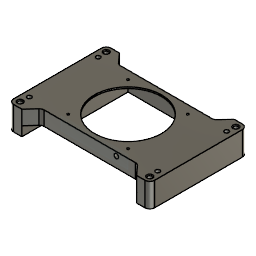
MPPT250 (Autodesk Fusion 360 design; units mm, degrees)
Autodesk Fusion 360 part; units mm, degrees
sketch "Skizze1" plane through (0, 0, 0) normal (0, 0, 1) x (1, 0, 0)
  line L0 (-137.5, 102) -> (137.5, 102)
  line L1 (147.5, 92) -> (147.5, -92)
  line L2 (137.5, -102) -> (-137.5, -102)
  line L3 (-147.5, -92) -> (-147.5, 92)
  line L4 (0, 102) -> (0, -102) construction
  line L5 (-147.5, 0) -> (147.5, 0) construction
  arc A0 (-137.5, 102) -> (-147.5, 92) centre (-137.5, 92) ccw
  arc A1 (-147.5, -92) -> (-137.5, -102) centre (-137.5, -92) ccw
  arc A2 (137.5, -102) -> (147.5, -92) centre (137.5, -92) ccw
  arc A3 (147.5, 92) -> (137.5, 102) centre (137.5, 92) ccw
  point P0 (-147.5, 102)
  point P1 (147.5, 102)
  point P2 (-147.5, -102)
  dimension "d1" = 295
  dimension "d2" = 204
  dimension "d3" = 10
  constraint horizontal L0
  constraint vertical L1
  constraint horizontal L2
  constraint vertical L3
  constraint midpoint L4 origin
  constraint coincident L0 L4.start
  constraint coincident L3 L5.start
  constraint coincident P0 L0
  constraint coincident P0 L3
  constraint tangent L0 A0
  constraint tangent L3 A0
  constraint coincident L2 L4.end
  constraint coincident P2 L2
  constraint coincident P2 L3
  constraint tangent L2 A1
  constraint tangent L3 A1
  constraint equal A0 A1
  constraint coincident L1 L5.end
  constraint tangent L1 A2
  constraint tangent L2 A2
  constraint equal A0 A2
  constraint coincident P1 L0
  constraint coincident P1 L1
  constraint tangent L0 A3
  constraint tangent L1 A3
  constraint equal A0 A3
  measures "d1" distance of P0 P1
  measures "d2" distance of P0 P2
  measures "d3" radius of A0
extrude "Extrusion1" add sketch "Skizze1" along normal blind 50
sketch "Skizze2" plane through (0, 0, 50) normal (0, 0, 1) x (-1, 0, 0)
  arc A0 (-137.5, 102) -> (-147.5, 92) centre (-137.5, 92) ccw
  line L0 (-147.5, 92) -> (-147.5, -92)
  arc A1 (-147.5, -92) -> (-137.5, -102) centre (-137.5, -92) ccw
  line L1 (-137.5, -102) -> (137.5, -102)
  arc A2 (137.5, -102) -> (147.5, -92) centre (137.5, -92) ccw
  line L2 (147.5, -92) -> (147.5, 92)
  arc A3 (147.5, 92) -> (137.5, 102) centre (137.5, 92) ccw
  line L3 (137.5, 102) -> (-137.5, 102)
  line L4 (134.3, -72.05) -> (-134.3, -72.05) construction
  line L5 (-134.3, -72.05) -> (-134.3, 72.05) construction
  line L6 (-134.3, 72.05) -> (134.3, 72.05) construction
  line L7 (134.3, 72.05) -> (134.3, -72.05) construction
  line L8 (134.3, 0) -> (-134.3, 0) construction
  line L9 (0, -72.05) -> (0, 72.05) construction
  dimension "d6" = 268.6
  dimension "d7" = 144.1
  constraint horizontal L4
  constraint vertical L5
  constraint horizontal L6
  constraint vertical L7
  constraint midpoint L7 L8.start
  constraint midpoint L5 L8.end
  constraint midpoint L4 L9.start
  constraint midpoint L6 L9.end
  constraint midpoint L8 origin
  measures "d6" distance of L4.start L4.end
  measures "d7" distance of L4.start L6.end
hole "Bohrung1" at (-134.3, 72.05, 50) at (134.3, 72.05, 50) at (134.3, -72.05, 50) at (-134.3, -72.05, 50) direction (0, 0, -1) diameter 8.8 depth 50 tip angle 180
sketch "Skizze3" plane through (0, 0, 50) normal (0, 0, 1) x (-1, 0, 0)
  circle A0 centre (-134.3, 72.05) radius 4.4
  circle A1 centre (134.3, -72.05) radius 4.4
  circle A2 centre (-134.3, -72.05) radius 4.4
  circle A3 centre (134.3, 72.05) radius 4.4
  arc A4 (-137.5, 102) -> (-147.5, 92) centre (-137.5, 92) ccw
  line L0 (-147.5, 92) -> (-147.5, -92)
  arc A5 (-147.5, -92) -> (-137.5, -102) centre (-137.5, -92) ccw
  line L1 (-137.5, -102) -> (137.5, -102)
  arc A6 (137.5, -102) -> (147.5, -92) centre (137.5, -92) ccw
  line L2 (147.5, -92) -> (147.5, 92)
  arc A7 (147.5, 92) -> (137.5, 102) centre (137.5, 92) ccw
  line L3 (137.5, 102) -> (-137.5, 102)
  line L4 (135.5, -90) -> (-135.5, -90) construction
  line L5 (-135.5, -90) -> (-135.5, 90) construction
  line L6 (-135.5, 90) -> (135.5, 90) construction
  line L7 (135.5, 90) -> (135.5, -90) construction
  line L8 (135.5, 0) -> (-135.5, 0) construction
  line L9 (0, -90) -> (0, 90) construction
  dimension "d11" = 271
  dimension "d12" = 180
  constraint horizontal L4
  constraint vertical L5
  constraint horizontal L6
  constraint vertical L7
  constraint midpoint L7 L8.start
  constraint midpoint L5 L8.end
  constraint midpoint L4 L9.start
  constraint midpoint L6 L9.end
  constraint midpoint L8 origin
  measures "d11" distance of L4.start L4.end
  measures "d12" distance of L4.start L6.end
hole "Bohrung2" at (-135.5, 90, 50) at (-135.5, -90, 50) at (135.5, -90, 50) at (135.5, 90, 50) direction (0, 0, -1) diameter 8.8 depth 50 tip angle 180 countersink diameter 12 countersink angle 90
sketch "Skizze4" plane through (0, 0, 50) normal (0, 0, 1) x (-1, 0, 0)
  circle A0 centre (-135.5, 90) radius 6
  circle A1 centre (135.5, -90) radius 6
  circle A2 centre (135.5, 90) radius 6
  circle A3 centre (-135.5, -90) radius 6
  circle A4 centre (-134.3, 72.05) radius 4.4
  circle A5 centre (134.3, -72.05) radius 4.4
  circle A6 centre (-134.3, -72.05) radius 4.4
  circle A7 centre (134.3, 72.05) radius 4.4
  arc A8 (-137.5, 102) -> (-147.5, 92) centre (-137.5, 92) ccw
  line L0 (-147.5, 92) -> (-147.5, -92)
  arc A9 (-147.5, -92) -> (-137.5, -102) centre (-137.5, -92) ccw
  line L1 (-137.5, -102) -> (137.5, -102)
  arc A10 (137.5, -102) -> (147.5, -92) centre (137.5, -92) ccw
  line L2 (147.5, -92) -> (147.5, 92)
  arc A11 (147.5, 92) -> (137.5, 102) centre (137.5, 92) ccw
  line L3 (137.5, 102) -> (-137.5, 102)
hole "Bohrung3" at (0, 0, 50) direction (0, 0, -1) diameter 140 depth 50 tip angle 180
sketch "Skizze5" plane through (0, 0, 50) normal (0, 0, 1) x (-1, 0, 0)
  circle A0 centre (0, 0) radius 70
  circle A1 centre (-135.5, 90) radius 6
  circle A2 centre (135.5, -90) radius 6
  circle A3 centre (135.5, 90) radius 6
  circle A4 centre (-135.5, -90) radius 6
  circle A5 centre (-134.3, 72.05) radius 4.4
  circle A6 centre (134.3, -72.05) radius 4.4
  circle A7 centre (-134.3, -72.05) radius 4.4
  circle A8 centre (134.3, 72.05) radius 4.4
  arc A9 (-137.5, 102) -> (-147.5, 92) centre (-137.5, 92) ccw
  line L0 (-147.5, 92) -> (-147.5, -92)
  arc A10 (-147.5, -92) -> (-137.5, -102) centre (-137.5, -92) ccw
  line L1 (-137.5, -102) -> (137.5, -102)
  arc A11 (137.5, -102) -> (147.5, -92) centre (137.5, -92) ccw
  line L2 (147.5, -92) -> (147.5, 92)
  arc A12 (147.5, 92) -> (137.5, 102) centre (137.5, 92) ccw
  line L3 (137.5, 102) -> (-137.5, 102)
  line L4 (62.5, -62.5) -> (-62.5, -62.5) construction
  line L5 (-62.5, -62.5) -> (-62.5, 62.5) construction
  line L6 (-62.5, 62.5) -> (62.5, 62.5) construction
  line L7 (62.5, 62.5) -> (62.5, -62.5) construction
  line L8 (62.5, 0) -> (-62.5, 0) construction
  line L9 (0, -62.5) -> (0, 62.5) construction
  dimension "d21" = 125
  dimension "d22" = 125
  constraint horizontal L4
  constraint vertical L5
  constraint horizontal L6
  constraint vertical L7
  constraint midpoint L7 L8.start
  constraint midpoint L5 L8.end
  constraint midpoint L4 L9.start
  constraint midpoint L6 L9.end
  constraint midpoint L9 A0.centre
  constraint coincident A0.centre origin
  measures "d21" distance of L4.start L4.end
  measures "d22" distance of L4.start L6.end
hole "Bohrung4" at (-62.5, 62.5, 50) at (62.5, 62.5, 50) at (62.5, -62.5, 50) at (-62.5, -62.5, 50) direction (0, 0, -1) diameter 4.3 depth 50 tip angle 180
sketch "Skizze6" plane through (0, 0, 0) normal (0, 0, -1) x (1, 0, 0)
  circle A0 centre (62.5, 62.5) radius 2.15
  circle A1 centre (-62.5, -62.5) radius 2.15
  circle A2 centre (62.5, -62.5) radius 2.15
  circle A3 centre (-62.5, 62.5) radius 2.15
  circle A4 centre (0, 0) radius 70
  circle A5 centre (135.5, 90) radius 4.4
  circle A6 centre (-135.5, -90) radius 4.4
  circle A7 centre (-135.5, 90) radius 4.4
  circle A8 centre (135.5, -90) radius 4.4
  circle A9 centre (134.3, 72.05) radius 4.4
  circle A10 centre (-134.3, -72.05) radius 4.4
  circle A11 centre (134.3, -72.05) radius 4.4
  circle A12 centre (-134.3, 72.05) radius 4.4
  arc A13 (147.5, 92) -> (137.5, 102) centre (137.5, 92) ccw
  line L0 (137.5, 102) -> (-137.5, 102)
  arc A14 (-137.5, 102) -> (-147.5, 92) centre (-137.5, 92) ccw
  line L1 (-147.5, 92) -> (-147.5, -92)
  arc A15 (-147.5, -92) -> (-137.5, -102) centre (-137.5, -92) ccw
  line L2 (-137.5, -102) -> (137.5, -102)
  arc A16 (137.5, -102) -> (147.5, -92) centre (137.5, -92) ccw
  line L3 (147.5, -92) -> (147.5, 92)
  line L4 (-70, 70) -> (70, 70)
  line L5 (70, 70) -> (70, -70)
  line L6 (70, -70) -> (-70, -70)
  line L7 (-70, -70) -> (-70, 70)
  line L8 (0, 70) -> (0, -70) construction
  line L9 (-70, 0) -> (70, 0) construction
  dimension "d26" = 140
  dimension "d27" = 140
  constraint horizontal L4
  constraint vertical L5
  constraint horizontal L6
  constraint vertical L7
  constraint midpoint L4 L8.start
  constraint perpendicular L4 L8
  constraint midpoint L7 L9.start
  constraint midpoint L5 L9.end
  constraint midpoint L9 A4.centre
  constraint coincident A4.centre origin
  measures "d26" distance of L4.start L4.end
  measures "d27" distance of L4.start L6.end
extrude "Extrusion2" cut sketch "Skizze6" against normal blind 47 contours A4 L5 L6 | A4 L4 L5 | A4 L4 L7 | A4 L6 L7
sketch "Skizze7" plane through (0, 0, 0) normal (0, 0, -1) x (1, 0, 0)
  line L0 (70, -70) -> (-70, -70)
  line L1 (-70, -70) -> (-70, 70)
  line L2 (-70, 70) -> (70, 70)
  line L3 (70, 70) -> (70, -70)
  circle A0 centre (135.5, 90) radius 4.4
  circle A1 centre (-135.5, -90) radius 4.4
  circle A2 centre (-135.5, 90) radius 4.4
  circle A3 centre (135.5, -90) radius 4.4
  circle A4 centre (134.3, 72.05) radius 4.4
  circle A5 centre (-134.3, -72.05) radius 4.4
  circle A6 centre (134.3, -72.05) radius 4.4
  circle A7 centre (-134.3, 72.05) radius 4.4
  arc A8 (147.5, 92) -> (137.5, 102) centre (137.5, 92) ccw
  line L4 (137.5, 102) -> (-137.5, 102)
  arc A9 (-137.5, 102) -> (-147.5, 92) centre (-137.5, 92) ccw
  line L5 (-147.5, 92) -> (-147.5, -92)
  arc A10 (-147.5, -92) -> (-137.5, -102) centre (-137.5, -92) ccw
  line L6 (-137.5, -102) -> (137.5, -102)
  arc A11 (137.5, -102) -> (147.5, -92) centre (137.5, -92) ccw
  line L7 (147.5, -92) -> (147.5, 92)
  line L8 (120, -102) -> (-120, -102)
  line L9 (-120, -102) -> (-120, 102)
  line L10 (-120, 102) -> (120, 102)
  line L11 (120, 102) -> (120, -102)
  line L12 (0, -102) -> (0, 102) construction
  line L13 (120, 0) -> (-120, 0) construction
  dimension "d30" = 240
  dimension "d31" = 204
  constraint horizontal L8
  constraint vertical L9
  constraint horizontal L10
  constraint vertical L11
  constraint midpoint L8 L12.start
  constraint midpoint L10 L12.end
  constraint midpoint L11 L13.start
  constraint midpoint L9 L13.end
  constraint midpoint L13 origin
  measures "d30" distance of L8.start L8.end
  measures "d31" distance of L8.start L10.end
extrude "Extrusion3" cut sketch "Skizze7" against normal blind 20 contours L4 L6 L8 L9 L10 L11
sketch "Skizze8" plane through (0, 0, 20) normal (0, 0, -1) x (1, 0, 0)
  line L0 (-70, 70) -> (70, 70)
  line L1 (70, 70) -> (70, -70)
  line L2 (70, -70) -> (-70, -70)
  line L3 (-70, -70) -> (-70, 70)
  line L4 (120, 102) -> (-120, 102)
  line L5 (-120, 102) -> (-120, -102)
  line L6 (-120, -102) -> (120, -102)
  line L7 (120, -102) -> (120, 102)
  line L8 (120, -102) -> (102.9757, -83.2733)
  line L9 (95.5763, -80) -> (-95.5763, -80)
  line L10 (-102.9757, -83.2733) -> (-120, -102)
  line L11 (120, 102) -> (102.9757, 83.2733)
  line L12 (95.5763, 80) -> (-95.5763, 80)
  line L13 (-102.9757, 83.2733) -> (-120, 102)
  arc A0 (102.9757, -83.2733) -> (95.5763, -80) centre (95.5763, -90) ccw
  arc A1 (-95.5763, -80) -> (-102.9757, -83.2733) centre (-95.5763, -90) ccw
  arc A2 (95.5763, 80) -> (102.9757, 83.2733) centre (95.5763, 90) ccw
  arc A3 (-102.9757, 83.2733) -> (-95.5763, 80) centre (-95.5763, 90) ccw
  dimension "d34" = 10
  constraint coincident L6.end L7.start
  constraint perpendicular L7 L9
  constraint coincident L5.end L6.start
  constraint coincident L4.start L7.end
  constraint parallel L10 L11
  constraint perpendicular L7 L12
  constraint coincident L4.end L5.start
  constraint tangent L8 A0
  constraint tangent L9 A0
  constraint tangent L9 A1
  constraint tangent L10 A1
  constraint equal A0 A1
  constraint tangent L11 A2
  constraint tangent L12 A2
  constraint equal A0 A2
  constraint tangent L12 A3
  constraint tangent L13 A3
  constraint equal A0 A3
  measures "d34" radius of A0
extrude "Extrusion4" cut sketch "Skizze8" against normal blind 50 contours L4 L11 L12 L13 A2 A3 | L6 L8 L9 L10 A0 A1
sketch "Skizze9" plane through (0, 0, 0) normal (0, 0, -1) x (1, 0, 0)
  line L0 (120, 102) -> (120, -102)
  line L1 (120, -102) -> (137.5, -102)
  arc A0 (137.5, -102) -> (147.5, -92) centre (137.5, -92) ccw
  line L2 (147.5, -92) -> (147.5, 92)
  arc A1 (147.5, 92) -> (137.5, 102) centre (137.5, 92) ccw
  line L3 (137.5, 102) -> (120, 102)
  circle A2 centre (135.5, 90) radius 4.4
  circle A3 centre (135.5, -90) radius 4.4
  circle A4 centre (134.3, 72.05) radius 4.4
  circle A5 centre (134.3, -72.05) radius 4.4
  line L4 (138.1971, -78.8) -> (142.0942, -72.05)
  line L5 (142.0942, -72.05) -> (138.1971, -65.3)
  line L6 (138.1971, -65.3) -> (130.4029, -65.3)
  line L7 (130.4029, -65.3) -> (126.5058, -72.05)
  line L8 (126.5058, -72.05) -> (130.4029, -78.8)
  line L9 (130.4029, -78.8) -> (138.1971, -78.8)
  line L10 (138.1971, 65.3) -> (142.0942, 72.05)
  line L11 (142.0942, 72.05) -> (138.1971, 78.8)
  line L12 (138.1971, 78.8) -> (130.4029, 78.8)
  line L13 (130.4029, 78.8) -> (126.5058, 72.05)
  line L14 (126.5058, 72.05) -> (130.4029, 65.3)
  line L15 (130.4029, 65.3) -> (138.1971, 65.3)
  point P0 (134.3, -72.05)
  point P1 (134.3, 72.05)
  dimension "d37" = 6.75
  dimension "d38" = 6.75
  constraint coincident P0 A5.centre
  constraint coincident P1 A4.centre
  measures "d37" distance of P0 L9
  measures "d38" distance of P1 L15
extrude "Extrusion5" cut sketch "Skizze9" against normal blind 6.7 contours L4 L5 L6 L7 L8 L9 | L10 L11 L12 L13 L14 L15
sketch "Skizze10" plane through (0, 0, 0) normal (0, 0, -1) x (1, 0, 0)
  line L0 (-120, -102) -> (-120, 102)
  line L1 (-120, 102) -> (-137.5, 102)
  arc A0 (-137.5, 102) -> (-147.5, 92) centre (-137.5, 92) ccw
  line L2 (-147.5, 92) -> (-147.5, -92)
  arc A1 (-147.5, -92) -> (-137.5, -102) centre (-137.5, -92) ccw
  line L3 (-137.5, -102) -> (-120, -102)
  circle A2 centre (-134.3, 72.05) radius 4.4
  circle A3 centre (-134.3, -72.05) radius 4.4
  circle A4 centre (-135.5, 90) radius 4.4
  circle A5 centre (-135.5, -90) radius 4.4
  line L4 (-138.3727, -65.4045) -> (-142.0916, -72.2543)
  line L5 (-142.0916, -72.2543) -> (-138.0188, -78.8998)
  line L6 (-138.0188, -78.8998) -> (-130.2273, -78.6955)
  line L7 (-130.2273, -78.6955) -> (-126.5084, -71.8457)
  line L8 (-126.5084, -71.8457) -> (-130.5812, -65.2002)
  line L9 (-130.5812, -65.2002) -> (-138.3727, -65.4045)
  line L10 (-130.4029, 65.3) -> (-126.5058, 72.05)
  line L11 (-126.5058, 72.05) -> (-130.4029, 78.8)
  line L12 (-130.4029, 78.8) -> (-138.1971, 78.8)
  line L13 (-138.1971, 78.8) -> (-142.0942, 72.05)
  line L14 (-142.0942, 72.05) -> (-138.1971, 65.3)
  line L15 (-138.1971, 65.3) -> (-130.4029, 65.3)
  point P0 (-134.3, -72.05)
  point P1 (-134.3, 72.05)
  dimension "d41" = 6.75
  dimension "d42" = 6.75
  constraint coincident P0 A3.centre
  constraint coincident P1 A2.centre
  measures "d41" distance of P0 L9
  measures "d42" distance of P1 L15
extrude "Extrusion6" cut sketch "Skizze10" against normal blind 6.7 contours L4 L5 L6 L7 L8 L9 | L10 L11 L12 L13 L14 L15
sketch "Skizze11" plane through (0, -70, 0) normal (0, 1, 0) x (-1, 0, 0)
  line L0 (-70, 20) -> (70, 20)
  line L1 (70, 20) -> (70, 47)
  line L2 (70, 47) -> (0, 47)
  line L3 (0, 47) -> (-70, 47)
  line L4 (-70, 47) -> (-70, 20)
hole "Bohrung5" at (55.5792, -70, 41.9512) direction (0, -1, 0) diameter 9.3 depth 50 tip angle 180
